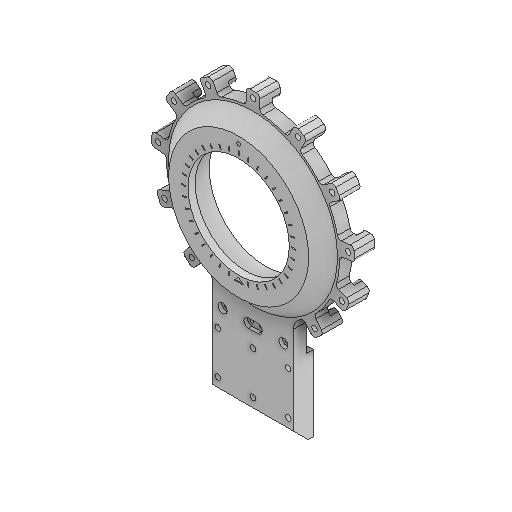
# Autodesk Inventor part: 3DP_PLA_B_Axis_Bearing_Mounting_Plate
Saved by Autodesk Inventor 2027 (Build 310192060, 192F)
## iProperties
Created: 2026-01-17
Part Number: 3DP_PLA_B_Axis_Bearing_Mounting_Plate
Material: Generic
Document SubType Name: Modeling
Designer: User
Density: 1 g/cm^3
Appearance: Default
Author: User
Autodesk Inventor part; units mm, degrees
ref_plane "YZ Plane" through (0, 0, 0) normal (1, 0, 0) x (0, 1, 0)
ref_plane "XZ Plane" through (0, 0, 0) normal (0, 1, 0) x (-1, 0, 0)
ref_plane "XY Plane" through (0, 0, 0) normal (0, 0, 1) x (1, 0, 0)
sketch "Sketch1" plane through (0, 0, 0) normal (0, 0, 1) x (1, 0, 0)
  circle A0 centre (0, 0) radius 96
  line L0 (-45, -84.7998) -> (-45, -207.5)
  line L1 (-45, -207.5) -> (45, -207.5)
  line L2 (45, -207.5) -> (45, -84.7998)
  circle A1 centre (0, 0) radius 62.6
  dimension "d0" = 192
  dimension "d1" = 90
  dimension "d2" = 45
  dimension "d3" = 111.5
  dimension "d4" = 125.2
  constraints: 6 end point, 2 centre point, 2 coincident, 2 perpendicular, 2 point on circle, 1 vertical
  measures "d0" diameter of A0
  measures "d1" distance between parallel lines of L2 L0
  measures "d2" distance from line of point (0, 0) L0
  measures "d3" distance edge to line of A0 L1
  measures "d4" diameter of A1
extrude "Extrusion1" add sketch "Sketch1" along normal blind 14
sketch "Sketch2" plane through (0, 0, 14) normal (0, 0, 1) x (1, 0, 0)
  line L0 (-45, -84.7998) -> (-45, -207.5) projected
  line L1 (-45, -207.5) -> (45, -207.5) projected
  line L2 (45, -207.5) -> (45, -84.7998) projected
  arc A0 (45, -84.7998) -> (-45, -84.7998) centre (0, 0) ccw projected
  circle A1 centre (0, 0) radius 62.6 projected
  circle A2 centre (0, 0) radius 77.6
  dimension "d7" = 15
  constraints: 1 centre point
  measures "d7" radial gap between concentric circles of A1 A2
extrude "Extrusion2" add sketch "Sketch2" along normal blind 8 contours A2
sketch "Sketch3" plane through (0, 0, 22) normal (0, 0, 1) x (1, 0, 0)
  circle A0 centre (0, 0) radius 77.6 projected
  circle A1 centre (0, 0) radius 62.6 projected
  circle A2 centre (0, 0) radius 56.15
  dimension "d10" = 112.3
  constraints: 1 centre point, 1 coincident
  measures "d10" diameter of A2
extrude "Extrusion3" add sketch "Sketch3" along normal blind 8 contours A0 | A1
sketch "Sketch4" plane through (0, 0, 0) normal (0, 0, -1) x (-1, 0, 0)
  line L0 (45, -84.7998) -> (45, -207.5) projected
  arc A0 (45, -84.7998) -> (-45, -84.7998) centre (0, 0) ccw projected
  line L1 (-45, -207.5) -> (-45, -84.7998) projected
  line L2 (45, -207.5) -> (-45, -207.5) projected
  circle A1 centre (0, 0) radius 62.6 projected
  line L3 (-45, -124) -> (45, -124)
  dimension "d13" = 83.5
  constraints: 2 end point, 2 point on line, 1 perpendicular
  measures "d13" distance between parallel lines of L2 L3
extrude "Extrusion4" add sketch "Sketch4" along normal blind 8 contours L0 L2 L1 L3
sketch "Sketch5" plane through (-45, -207.5, 14) normal (0, -1, 0) x (1, 0, 0)
  circle A0 centre (64.5, -22.5) radius 13.625
  circle A1 centre (25.5, -22.5) radius 13.625
  line L0 (90, -22) -> (90, 0) projected
  line L1 (0, 0) -> (90, 0) projected
  line L2 (0, -22) -> (0, 0) projected
  line L3 (90, -22) -> (0, -22) projected
  point P0 (45, -14)
  dimension "d16" = 27.25
  dimension "d17" = 27.25
  dimension "d18" = 0.5
  dimension "d19" = 0.5
  dimension "d20" = 39
  dimension "d21" = 90
  dimension "d22" = 25.5
  constraints: 2 centre point
  measures "d16" diameter of A0
  measures "d17" diameter of A1
  measures "d18" distance from line of L3 A0.centre
  measures "d19" distance from line of A1.centre L3
  measures "d20" distance of A1.centre A0.centre
  measures "d21" distance between parallel lines of L0 L2
  measures "d22" distance from line of L2 A1.centre
extrude "Extrusion5" cut sketch "Sketch5" against normal up to surface (83.5 mm away) contours A0 L3 | L3 A0 | L3 A1 | A1 L3
chamfer "Chamfer1" distance 16 angle 45 1 edges at (0, -207.5, 14)
sketch "Sketch6" plane through (0, 0, 14) normal (0, 0, 1) x (1, 0, 0)
  line L0 (45, -124) -> (30.1485, -124) projected
  line L1 (8.8515, -124) -> (-8.8515, -124) projected
  line L2 (-30.1485, -124) -> (-45, -124) projected
  line L3 (-33.1158, -124) -> (-33.1158, -207.5) projected
  line L4 (-33.1158, -207.5) -> (-45, -207.5) projected
  line L5 (-45, -207.5) -> (-45, -124) projected
  line L6 (-45, -124) -> (-33.1158, -124) projected
  line L7 (-45, -84.7998) -> (-45, -207.5) projected
  line L8 (-5.8842, -207.5) -> (-5.8842, -124) projected
  line L9 (-5.8842, -124) -> (5.8842, -124) projected
  line L10 (5.8842, -124) -> (5.8842, -207.5) projected
  line L11 (5.8842, -207.5) -> (-5.8842, -207.5) projected
  line L12 (33.1158, -207.5) -> (33.1158, -124) projected
  line L13 (33.1158, -124) -> (45, -124) projected
  line L14 (45, -124) -> (45, -207.5) projected
  line L15 (45, -207.5) -> (33.1158, -207.5) projected
  line L16 (45, -191.5) -> (-45, -191.5) projected
  point P0 (0, 0)
  point P1 (-39.0579, -134)
  point P2 (-39.0579, -181.5)
  point P3 (0, -134)
  point P4 (0, -181.5)
  point P5 (39.0579, -134)
  point P6 (39.0579, -181.5)
  dimension "d28" = 10
  dimension "d29" = 10
  dimension "d30" = 11.8842
  dimension "d31" = 11.8842
  dimension "d32" = 11.7683
  dimension "d33" = 5.9421
  dimension "d34" = 5.9421
  dimension "d35" = 5.8842
  constraints: 4 horizontal alignment, 3 vertical alignment
  measures "d28" distance from line of L2 point (-39.058, -134)
  measures "d29" distance from line of L16 point (-39.058, -181.5)
  measures "d30" distance between parallel lines of L7 L3
  measures "d31" distance between parallel lines of L14 L12
  measures "d32" distance between parallel lines of L10 L8
  measures "d33" distance from line of L7 point (-39.058, -134)
  measures "d34" distance from line of L14 point (39.058, -134)
  measures "d35" distance from line of L10 point (0, -134)
hole "Hole1" at (-39.0579, -134, 14) at (-39.0579, -181.5, 14) at (0, -134, 14) at (0, -181.5, 14) at (39.0579, -134, 14) at (39.0579, -181.5, 14) direction (0, 0, -1) diameter 6.2 end through all
sketch "Sketch7" plane through (0, 0, 14) normal (0, 0, 1) x (1, 0, 0)
  circle A0 centre (39.0579, -181.5) radius 3.1 projected
  circle A1 centre (39.0579, -134) radius 3.1 projected
  circle A2 centre (0, -181.5) radius 3.1 projected
  circle A3 centre (0, -134) radius 3.1 projected
  circle A4 centre (-39.0579, -181.5) radius 3.1 projected
  circle A5 centre (-39.0579, -134) radius 3.1 projected
  line L0 (45, -191.5) -> (45, -84.7998) projected
  arc A6 (45, -84.7998) -> (-45, -84.7998) centre (0, 0) ccw projected
  line L1 (-45, -84.7998) -> (-45, -191.5) projected
  circle A7 centre (0, 0) radius 77.6 projected
  line L2 (-7.5, 95.7066) -> (-7.5, 113)
  line L3 (-7.5, 113) -> (7.5, 113)
  line L4 (7.5, 113) -> (7.5, 95.7066)
  circle A8 centre (0, 106) radius 3.1
  arc A9 (48, -86.5852) -> (-48, -86.5852) centre (0, 0) ccw
  line L5 (48, -86.5852) -> (48, -190.5)
  line L6 (48, -190.5) -> (-48, -190.5)
  line L7 (-48, -190.5) -> (-48, -86.5852)
  line L8 (45, -191.5) -> (-45, -191.5) projected
  point P0 (-7.5, 98.7155)
  point P1 (7.5, 98.7155)
  dimension "d43" = 15
  dimension "d44" = 113
  dimension "d45" = 7.5
  dimension "d46" = 6.2
  dimension "d47" = 7
  dimension "d48" = 96
  dimension "d51" = 3
  dimension "d56" = 99
  constraints: 12 end point, 4 point on circle, 2 centre point, 2 perpendicular, 1 vertical, 1 other
  measures "d43" distance between parallel lines of L4 L2
  measures "d44" distance from line of L3 A6.centre
  measures "d45" distance from line of point (0, 0) L2
  measures "d46" diameter of A8
  measures "d47" distance from line of L3 A8.centre
  measures "d48" radius of A6
  measures "d51" radial gap between concentric circles of A6 A9
  measures "d56" radius of A9
extrude "Extrusion6" add sketch "Sketch7" against normal up to surface (14 mm away) contours A6 L2 A9 L4 | A9 L2 L3 L4
extrude "Extrusion7" add sketch "Sketch7" against normal blind 22.5 contours A9 L2 L3 L4
fillet "Fillet1" radius 4 4 edges at (7.5, 98.7155, -4.25) (-7.5, 98.7155, -4.25) (7.5, 113, 2.75) (-7.5, 113, 2.75)
fillet "Fillet2" radius 4 2 edges at (7.5, 95.7066, 7) (-7.5, 95.7066, 7)
pattern_circular "Circular Pattern1" count 6 over 140 about axis through (0, 0, 0) along (0, 0, 1) of "Extrusion6", "Extrusion7", "Fillet1", "Fillet2"
pattern_circular "Circular Pattern2" count 6 over 140 about axis through (0, 0, 0) along (0, 0, -1) of "Extrusion6", "Extrusion7", "Fillet1", "Fillet2"
chamfer "Chamfer2" distance 16 angle 45 1 edges at (-77.6, 0, 14)
fillet "Fillet3" radius 15 2 edges at (-45, -84.7998, 7) (45, -84.7998, 7)
sketch "Sketch8" plane through (0, 0, 0) normal (0, 0, -1) x (-1, 0, 0)
  arc A0 (3.3641, 98.9428) -> (-3.3641, 98.9428) centre (0, 0) ccw projected
  arc A1 (-7.5, 102.9405) -> (-3.3641, 98.9428) centre (-3.5, 102.9405) ccw projected
  line L0 (-7.5, 102.9405) -> (-7.5, 99.3365) projected
  arc A2 (-11.04, 95.3631) -> (-7.5, 99.3365) centre (-11.5, 99.3365) ccw projected
  arc A3 (-11.04, 95.3631) -> (-35.0225, 89.3836) centre (0, 0) ccw projected
  arc A4 (-40.0136, 91.23) -> (-35.0225, 89.3836) centre (-36.4818, 93.1079) ccw projected
  line L1 (-40.0136, 91.23) -> (-41.7055, 94.4121) projected
  arc A5 (-43.4805, 88.9407) -> (-41.7055, 94.4121) centre (-45.2373, 92.5342) ccw projected
  arc A6 (-43.4805, 88.9407) -> (-49.4211, 85.782) centre (0, 0) ccw projected
  arc A7 (-54.9498, 87.37) -> (-49.4211, 85.782) centre (-51.418, 89.2479) ccw projected
  line L2 (-54.9498, 87.37) -> (-53.2578, 84.1879) projected
  arc A8 (-54.518, 79.0176) -> (-53.2578, 84.1879) centre (-56.7896, 82.31) ccw projected
  arc A9 (-54.518, 79.0176) -> (-72.8861, 62.4789) centre (0, 0) ccw projected
  arc A10 (-78.1598, 61.7661) -> (-72.8861, 62.4789) centre (-75.923, 65.0822) ccw projected
  line L3 (-78.1598, 61.7661) -> (-81.1476, 63.7814) projected
  arc A11 (-80.1462, 58.1171) -> (-81.1476, 63.7814) centre (-83.3844, 60.4652) ccw projected
  arc A12 (-80.1462, 58.1171) -> (-83.9085, 52.5392) centre (0, 0) ccw projected
  arc A13 (-89.5355, 51.3458) -> (-83.9085, 52.5392) centre (-87.2987, 54.662) ccw projected
  line L4 (-89.5355, 51.3458) -> (-86.5477, 49.3305) projected
  arc A14 (-85.2331, 44.1738) -> (-86.5477, 49.3305) centre (-88.7844, 46.0144) ccw projected
  arc A15 (-85.2331, 44.1738) -> (-93.6867, 20.9477) centre (0, 0) ccw projected
  arc A16 (-98.0084, 17.8424) -> (-93.6867, 20.9477) centre (-97.5903, 21.8205) ccw projected
  line L5 (-98.0084, 17.8424) -> (-101.5926, 18.2191) projected
  arc A17 (-98.0492, 13.688) -> (-101.5926, 18.2191) centre (-102.0107, 14.241) ccw projected
  arc A18 (-98.0492, 13.688) -> (-98.7524, 6.9967) centre (0, 0) ccw projected
  arc A19 (-103.1606, 3.3013) -> (-98.7524, 6.9967) centre (-102.7424, 7.2794) ccw projected
  line L6 (-103.1606, 3.3013) -> (-99.5763, 2.9246) projected
  arc A20 (-95.9947, -1.0114) -> (-99.5763, 2.9246) centre (-99.9945, -1.0535) ccw projected
  arc A21 (-95.9947, -1.0114) -> (-92.5548, -25.4875) centre (0, 0) ccw projected
  arc A22 (-94.9128, -30.2582) -> (-92.5548, -25.4875) centre (-96.4112, -26.5495) ccw projected
  line L7 (-94.9128, -30.2582) -> (-98.2543, -31.6083) projected
  arc A23 (-92.9984, -33.9455) -> (-98.2543, -31.6083) centre (-96.7559, -35.3171) ccw projected
  arc A24 (-92.9984, -33.9455) -> (-90.478, -40.1838) centre (0, 0) ccw projected
  arc A25 (-92.6352, -45.5161) -> (-90.478, -40.1838) centre (-94.1337, -41.8073) ccw projected
  line L8 (-92.6352, -45.5161) -> (-89.2937, -44.166) projected
  arc A26 (-84.2835, -45.9598) -> (-89.2937, -44.166) centre (-87.7953, -47.8747) ccw projected
  arc A27 (-84.2835, -45.9598) -> (-69.7553, -65.956) centre (0, 0) ccw projected
  arc A28 (-69.5976, -71.2753) -> (-69.7553, -65.956) centre (-72.6618, -68.7042) ccw projected
  line L9 (-69.5976, -71.2753) -> (-71.9142, -74.0361) projected
  arc A29 (-66.1763, -73.6322) -> (-71.9142, -74.0361) centre (-68.85, -76.6073) ccw projected
  arc A30 (-66.1763, -73.6322) -> (-61.0222, -77.957) centre (0, 0) ccw projected
  arc A31 (-60.4236, -83.6779) -> (-61.0222, -77.957) centre (-63.4877, -81.1068) ccw projected
  line L10 (-60.4236, -83.6779) -> (-58.107, -80.9171) projected
  arc A32 (-52.8411, -80.1487) -> (-58.107, -80.9171) centre (-55.0428, -83.4883) ccw projected
  arc A33 (-52.8411, -80.1487) -> (-51.8919, -80.7665) centre (0, 0) ccw projected
  arc A34 (-45, -93.3863) -> (-51.8919, -80.7665) centre (-60, -93.3863) ccw projected
  line L11 (-45, -124) -> (-45, -93.3863) projected
  line L12 (-45, -124) -> (-30.1485, -124) projected
  line L13 (-30.1485, -124) -> (-8.8515, -124) projected
  line L14 (-8.8515, -124) -> (8.8515, -124) projected
  line L15 (8.8515, -124) -> (30.1485, -124) projected
  line L16 (30.1485, -124) -> (45, -124) projected
  line L17 (45, -93.3863) -> (45, -124) projected
  arc A35 (51.8919, -80.7665) -> (45, -93.3863) centre (60, -93.3863) ccw projected
  arc A36 (51.8919, -80.7665) -> (52.8411, -80.1487) centre (0, 0) ccw projected
  arc A37 (58.107, -80.9171) -> (52.8411, -80.1487) centre (55.0428, -83.4883) ccw projected
  line L18 (58.107, -80.9171) -> (60.4236, -83.6779) projected
  arc A38 (61.0222, -77.957) -> (60.4236, -83.6779) centre (63.4877, -81.1068) ccw projected
  arc A39 (61.0222, -77.957) -> (66.1763, -73.6322) centre (0, 0) ccw projected
  arc A40 (71.9142, -74.0361) -> (66.1763, -73.6322) centre (68.85, -76.6073) ccw projected
  line L19 (71.9142, -74.0361) -> (69.5976, -71.2753) projected
  arc A41 (69.7553, -65.956) -> (69.5976, -71.2753) centre (72.6618, -68.7042) ccw projected
  arc A42 (69.7553, -65.956) -> (84.2835, -45.9598) centre (0, 0) ccw projected
  arc A43 (89.2937, -44.166) -> (84.2835, -45.9598) centre (87.7953, -47.8747) ccw projected
  line L20 (89.2937, -44.166) -> (92.6352, -45.5161) projected
  arc A44 (90.478, -40.1838) -> (92.6352, -45.5161) centre (94.1337, -41.8073) ccw projected
  arc A45 (90.478, -40.1838) -> (92.9984, -33.9455) centre (0, 0) ccw projected
  arc A46 (98.2543, -31.6083) -> (92.9984, -33.9455) centre (96.7559, -35.3171) ccw projected
  line L21 (98.2543, -31.6083) -> (94.9128, -30.2582) projected
  arc A47 (92.5548, -25.4875) -> (94.9128, -30.2582) centre (96.4112, -26.5495) ccw projected
  arc A48 (92.5548, -25.4875) -> (95.9947, -1.0114) centre (0, 0) ccw projected
  arc A49 (99.5763, 2.9246) -> (95.9947, -1.0114) centre (99.9945, -1.0535) ccw projected
  line L22 (99.5763, 2.9246) -> (103.1606, 3.3013) projected
  arc A50 (98.7524, 6.9967) -> (103.1606, 3.3013) centre (102.7424, 7.2794) ccw projected
  arc A51 (98.7524, 6.9967) -> (98.0492, 13.688) centre (0, 0) ccw projected
  arc A52 (101.5926, 18.2191) -> (98.0492, 13.688) centre (102.0107, 14.241) ccw projected
  line L23 (101.5926, 18.2191) -> (98.0084, 17.8424) projected
  arc A53 (93.6867, 20.9477) -> (98.0084, 17.8424) centre (97.5903, 21.8205) ccw projected
  arc A54 (93.6867, 20.9477) -> (85.2331, 44.1738) centre (0, 0) ccw projected
  arc A55 (86.5477, 49.3305) -> (85.2331, 44.1738) centre (88.7844, 46.0144) ccw projected
  line L24 (86.5477, 49.3305) -> (89.5355, 51.3458) projected
  arc A56 (83.9085, 52.5392) -> (89.5355, 51.3458) centre (87.2987, 54.662) ccw projected
  arc A57 (83.9085, 52.5392) -> (80.1462, 58.1171) centre (0, 0) ccw projected
  arc A58 (81.1476, 63.7814) -> (80.1462, 58.1171) centre (83.3844, 60.4652) ccw projected
  line L25 (81.1476, 63.7814) -> (78.1598, 61.7661) projected
  arc A59 (72.8861, 62.4789) -> (78.1598, 61.7661) centre (75.923, 65.0822) ccw projected
  arc A60 (72.8861, 62.4789) -> (54.518, 79.0176) centre (0, 0) ccw projected
  arc A61 (53.2578, 84.1879) -> (54.518, 79.0176) centre (56.7896, 82.31) ccw projected
  line L26 (53.2578, 84.1879) -> (54.9498, 87.37) projected
  arc A62 (49.4211, 85.782) -> (54.9498, 87.37) centre (51.418, 89.2479) ccw projected
  arc A63 (49.4211, 85.782) -> (43.4805, 88.9407) centre (0, 0) ccw projected
  arc A64 (41.7055, 94.4121) -> (43.4805, 88.9407) centre (45.2373, 92.5342) ccw projected
  line L27 (41.7055, 94.4121) -> (40.0136, 91.23) projected
  arc A65 (35.0225, 89.3836) -> (40.0136, 91.23) centre (36.4818, 93.1079) ccw projected
  arc A66 (35.0225, 89.3836) -> (11.04, 95.3631) centre (0, 0) ccw projected
  arc A67 (7.5, 99.3365) -> (11.04, 95.3631) centre (11.5, 99.3365) ccw projected
  line L28 (7.5, 99.3365) -> (7.5, 102.9405) projected
  arc A68 (3.3641, 98.9428) -> (7.5, 102.9405) centre (3.5, 102.9405) ccw projected
  circle A69 centre (0, 0) radius 62.6 projected
  line L29 (-33.1158, -207.5) -> (-33.1158, -124) projected
  line L30 (-5.8842, -124) -> (-5.8842, -207.5) projected
  line L31 (-19.5, -124) -> (-19.5, -108)
  line L32 (5.8842, -207.5) -> (5.8842, -124) projected
  line L33 (33.1158, -124) -> (33.1158, -207.5) projected
  line L34 (19.5, -124) -> (19.5, -108)
  point P0 (-33.7, -112.6)
  point P1 (-5.3, -112.6)
  point P2 (5.3, -112.6)
  point P3 (33.7, -112.6)
  dimension "d67" = 11.4
  dimension "d68" = 27.2316
  dimension "d69" = 13.6158
  dimension "d70" = 14.2
  dimension "d71" = 14.2
  dimension "d79" = 27.2316
  dimension "d80" = 13.6158
  dimension "d81" = 11.4
  dimension "d82" = 14.2
  dimension "d83" = 14.2
  constraints: 4 end point, 2 horizontal alignment, 2 midpoint, 2 vertical
  measures "d67" distance from line of L13 point (-33.7, -112.6)
  measures "d68" distance between parallel lines of L29 L30
  measures "d69" distance between parallel lines of L30 L31
  measures "d70" distance from line of point (-33.7, -112.6) L31
  measures "d71" distance from line of L31 point (-5.3, -112.6)
  measures "d79" distance between parallel lines of L33 L32
  measures "d80" distance between parallel lines of L34 L33
  measures "d81" distance from line of L15 point (5.3, -112.6)
  measures "d82" distance from line of L34 point (5.3, -112.6)
  measures "d83" distance from line of L34 point (33.7, -112.6)
hole "Hole2" at (33.7, -112.6, 0) at (5.3, -112.6, 0) at (-5.3, -112.6, 0) at (-33.7, -112.6, 0) direction (0, 0, 1) diameter 4.2 end through all
sketch "Sketch9" plane through (0, 0, 14) normal (0, 0, 1) x (1, 0, 0)
  circle A0 centre (-33.7, -112.6) radius 2.1 projected
  circle A1 centre (-5.3, -112.6) radius 2.1 projected
  circle A2 centre (5.3, -112.6) radius 2.1 projected
  circle A3 centre (33.7, -112.6) radius 2.1 projected
  circle A4 centre (-33.7, -112.6) radius 5
  circle A5 centre (-5.3, -112.6) radius 5
  circle A6 centre (5.3, -112.6) radius 5
  circle A7 centre (33.7, -112.6) radius 5
  line L0 (-5.3, -107.6) -> (5.3, -107.6)
  line L1 (-5.3, -117.6) -> (5.3, -117.6)
  point P0 (0, 0)
  dimension "d84" = 10
  dimension "d85" = 10
  dimension "d86" = 10
  dimension "d87" = 10
  constraints: 4 centre point, 4 coincident, 4 end point, 4 point on circle, 1 horizontal, 1 tangent
  measures "d84" diameter of A4
  measures "d85" diameter of A5
  measures "d86" diameter of A6
  measures "d87" diameter of A7
extrude "Extrusion8" cut sketch "Sketch9" against normal blind 4
sketch "Sketch10" plane through (0, 0, 30) normal (0, 0, 1) x (1, 0, 0)
  circle A0 centre (0, 0) radius 62.6 projected
  circle A1 centre (0, 0) radius 77.6 projected
  point P0 (0, 70)
  dimension "d90" = 125.2
  dimension "d91" = 155.2
  dimension "d92" = 70
  measures "d90" diameter of A0
  measures "d91" diameter of A1
  measures "d92" distance of point (0, 0) point (0, 70)
hole "Hole3" at (0, 70, 30) direction (0, 0, -1) diameter 4.134 depth 14.2 tip angle 118 thread size "M5x0.8" class "6H" standard "ISO Metric profile"
sketch "Sketch11" plane through (0, 0, 30) normal (0, 0, 1) x (1, 0, 0)
  circle A0 centre (0, 70) radius 2.067 projected
  circle A1 centre (0, 0) radius 77.6 projected
  circle A2 centre (0, 0) radius 56.15 projected
  line L0 (0, -58) -> (-5, -63)
  line L1 (-5, -63) -> (5, -63)
  line L2 (5, -63) -> (0, -58)
  dimension "d100" = 10
  dimension "d101" = 45
  dimension "d102" = 45
  dimension "d103" = 5
  dimension "d104" = 58
  constraints: 6 end point, 1 horizontal
  measures "d100" distance of L0.end L1.end
  measures "d101" angle of L1 L0
  measures "d102" angle of L1 L2
  measures "d103" horizontal distance of point (0, 0) L0.end
  measures "d104" distance of point (0, 0) L0.start
extrude "Extrusion9" cut sketch "Sketch11" against normal blind 1 contours L2 L1 L0
sketch "Sketch12" plane through (0, 0, 30) normal (0, 0, 1) x (1, 0, 0)
  line L0 (-0.5, 63) -> (0.5, 63)
  line L1 (0.5, 63) -> (0.5, 58.5)
  line L2 (0.5, 58.5) -> (-0.5, 58.5)
  line L3 (-0.5, 58.5) -> (-0.5, 63)
  point P0 (0, 0)
  dimension "d107" = 1
  dimension "d108" = 58.5
  dimension "d109" = 0.5
  dimension "d110" = 4.5
  constraints: 8 end point, 2 parallel, 1 horizontal, 1 perpendicular
  measures "d107" distance between parallel lines of L1 L3
  measures "d108" distance from line of point (0, 0) L2
  measures "d109" distance from line of point (0, 0) L3
  measures "d110" distance between parallel lines of L2 L0
extrude "Extrusion10" cut sketch "Sketch12" against normal blind 1
pattern_circular "Circular Pattern3" count 36 over 360 about axis through (0, 0, 22) along (0, 0, 1) of "Extrusion10"
equation "\"d2\" = 0.5 * d1"
equation "\"d17\" = d16"
equation "\"d19\" = d18"
equation "\"d22\" = -0.5 * d20 + 0.5 * d21"
equation "\"d29\" = d28"
equation "\"d33\" = 0.5 * d30"
equation "\"d34\" = 0.5 * d31"
equation "\"d35\" = 0.5 * d32"
equation "\"d45\" = 0.5 * d43"
equation "\"d69\" = 0.5 * d68"
equation "\"d71\" = d70"
equation "\"d80\" = 0.5 * d79"
equation "\"d81\" = d67"
equation "\"d82\" = d71"
equation "\"d83\" = d82"
equation "\"d102\" = d101"
body "Solid1"
